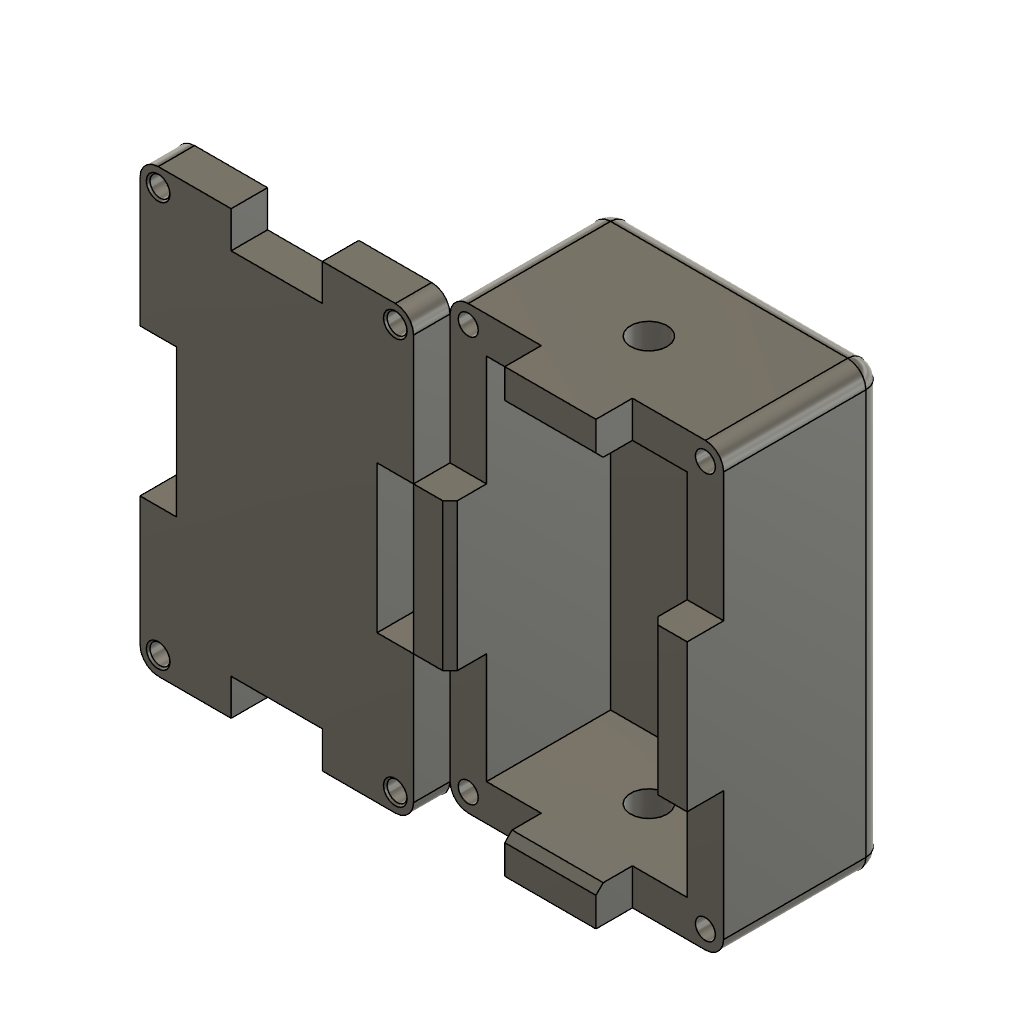
v1_caja (Autodesk Fusion 360 design; units mm, degrees)
part number: 2026-10-22-22-34-57-953
Autodesk Fusion 360 part; units mm, degrees
sketch "Sketch1" plane through (0, 0, 0) normal (0, 1, 0) x (1, 0, 0)
  line L0 (0, 0) -> (55, 0)
  line L1 (0, 0) -> (0, -101)
  line L2 (0, -101) -> (55, -101)
  line L3 (55, -101) -> (55, 0)
  dimension "d1" = 55
  dimension "d2" = 101
  dimension "d3" = 55
  constraint coincident L0.start L1.start
  constraint horizontal L0
  constraint perpendicular L0 L1
  constraint perpendicular L1 L2
  measures "d1" distance of L0.start L0.end
  measures "d2" distance of L0.start L1.end
  measures "d3" distance of L1.end L2.end
sketch "Sketch4" plane through (0, 0, 0) normal (0, 1, 0) x (1, 0, 0)
  line L0 (-10, 10) -> (65, 10)
  line L1 (-10, 10) -> (-10, -111)
  line L2 (65, 10) -> (65, -111)
  line L3 (65, -111) -> (-10, -111)
  dimension "d10" = 75
  dimension "d11" = 121
  dimension "d12" = 121
  constraint horizontal L0
  constraint perpendicular L0 L1
  constraint perpendicular L0 L2
  measures "d10" distance of L0.start L0.end
  measures "d11" distance of L0.start L1.end
  measures "d12" distance of L0.end L2.end
extrude "Extrude2" add sketch "Sketch4" along normal blind 54 makes body 1
move_body "Move3" bodies 1 to x (1, 0, 0) y (0, 1, 0) z (0, 0, 1) at (10, 0, 10)
sketch "Sketch5" plane through (0, 54, 0) normal (0, 1, 0) x (-1, 0, 0)
  line L0 (0, 0) -> (0, 121)
  line L1 (0, 121) -> (-75, 121)
  line L2 (-75, 121) -> (-75, 0)
  line L3 (-75, 0) -> (0, 0)
  line L4 (0, 121) -> (-25, 121)
  line L5 (-25, 121) -> (-25, 111)
  line L6 (-25, 111) -> (-50, 111)
  line L7 (-50, 111) -> (-50, 121)
  line L8 (-50, 121) -> (-75, 121)
  line L9 (-75, 121) -> (-75, 80.6667)
  line L10 (-75, 80.6667) -> (-65, 80.6667)
  line L11 (-65, 80.6667) -> (-65, 40.3333)
  line L12 (-65, 40.3333) -> (-75, 40.3333)
  line L13 (-75, 40.3333) -> (-75, 0)
  line L14 (0, 121) -> (0, 80.6667)
  line L15 (0, 80.6667) -> (-10, 80.6667)
  line L16 (-10, 80.6667) -> (-10, 40.3333)
  line L17 (-10, 40.3333) -> (0, 40.3333)
  line L18 (0, 40.3333) -> (0, 0)
  line L19 (0, 0) -> (-25, 0)
  line L20 (-25, 0) -> (-25, 10)
  line L21 (-25, 10) -> (-50, 10)
  line L22 (-50, 10) -> (-50, 0)
  line L23 (-50, 0) -> (-75, 0)
  dimension "d15" = 75
  dimension "d17" = 25
  dimension "d18" = 10
  dimension "d19" = 25
  dimension "d20" = 40.3333
  dimension "d21" = 40.3333
  dimension "d22" = 40.3333
  dimension "d23" = 40.3333
  dimension "d24" = 10
  dimension "d25" = 40.3333
  dimension "d26" = 40.3333
  dimension "d27" = 25
  dimension "d28" = 10
  dimension "d29" = 25
  constraint coincident L0.end L1.start
  constraint perpendicular L4 L5
  constraint perpendicular L5 L6
  constraint coincident L1.end L2.start
  constraint perpendicular L10 L11
  constraint coincident L2.end L3.start
  constraint perpendicular L4 L14
  constraint perpendicular L0 L15
  constraint perpendicular L15 L16
  constraint coincident L0.start L3.end
  constraint perpendicular L3 L20
  constraint perpendicular L20 L21
  measures "d15" distance of L0.start L2.end
  measures "d17" distance of L0.end L4.end
  measures "d18" distance of L4.end L5.end
  measures "d19" distance of L5.end L6.end
  measures "d20" distance of L1.end L9.end
  measures "d21" distance of L10.end L11.end
  measures "d22" distance of L12.end L2.end
  measures "d23" distance of L0.end L14.end
  measures "d24" distance of L14.end L15.end
  measures "d25" distance of L15.end L16.end
  measures "d26" distance of L17.end L0.start
  measures "d27" distance of L0.start L19.end
  measures "d28" distance of L19.end L20.end
  measures "d29" distance of L20.end L21.end
extrude "Extrude3" cut sketch "Sketch5" against normal blind 10 contours L0 L1 L2 L3 L4 L5 L6 L7 L8 L9 L10 L11 L12 L13 L14 L15 L16 L17 L18 L19 L20 L21 L22 L23 bodies 1
extrude "Extrude4" add sketch "Sketch5" against normal blind 10 separate body contours L0 L1 L2 L3 L4 L5 L6 L7 L8 L9 L10 L11 L12 L13 L14 L15 L16 L17 L18 L19 L20 L21 L22 L23 makes body 2
move_body "Move4" bodies 2 to x (1, 0, 0) y (0, 1, 0) z (0, 0, 1) at (0, 10, 0)
move_body "Move5" bodies 2 to x (1, 0, 0) y (0, 1, 0) z (0, 0, 1) at (-75, 0, 0)
extrude "Extrude5" add sketch "Sketch1" along normal blind 34 separate body makes body 3
move_body "Move6" bodies 3 to x (1, 0, 0) y (0, 1, 0) z (0, 0, 1) at (10, 0, 0)
move_body "Move7" bodies 3 to x (1, 0, 0) y (0, 1, 0) z (0, 0, 1) at (0, 10, 0)
move_body "Move8" bodies 3 to x (1, 0, 0) y (0, 1, 0) z (0, 0, 1) at (0, 0, 10)
combine "Combine1" operation cut target body 1 tool bodies 3
move_body "Move9" bodies 1 to x (1, 0, 0) y (0, 0, 1) z (0, -1, 0) at (0, 120.5, 0.5)
move_body "Move10" bodies 2 to x (1, 0, 0) y (0, 0, 1) z (0, -1, 0) at (0, 124.5, -3.5)
move_body "Move11" bodies 2 to x (1, 0, 0) y (0, 1, 0) z (0, 0, 1) at (0, -16.492, 0)
move_body "Move12" bodies 2 to x (1, 0, 0) y (0, 1, 0) z (0, 0, 1) at (0, 16.492, 0)
move_body "Move13" bodies 1 to x (1, 0, 0) y (0, 1, 0) z (0, 0, 1) at (0, 0.5, 0)
move_body "Move14" bodies 2 to x (1, 0, 0) y (0, 1, 0) z (0, 0, 1) at (0, -3.5, 0)
sketch "Sketch6" plane through (0, 0, 0.5) normal (0, 0, -1) x (-1, 0, 0)
  line L0 (0, 0) -> (0, 121)
  line L1 (0, 121) -> (-75, 121)
  line L2 (-75, 121) -> (-75, 0)
  line L3 (-75, 0) -> (0, 0)
  circle A0 centre (-37.5, 60.5) radius 7.5
  dimension "d36" = 15
  measures "d36" diameter of A0
copy_body "CopyPasteBodies1" bodies 1 makes body 4
extrude "Extrude6" cut sketch "Sketch6" against normal blind 10 contours A0 bodies 1
fillet "Fillet1" radius 5 1 edges at (37.5, 121, 0.5) on bodies 1
fillet "Fillet2" radius 5 3 edges at (0, 58, 0.5) (0, 119.5355, 1.9645) (0, 121, 25) on bodies 1
fillet "Fillet3" radius 5 3 edges at (75, 121, 25) (75, 119.5355, 1.9645) (75, 58, 0.5) on bodies 1
fillet "Fillet4" radius 5 5 edges at (75, 0, 25) (73.5355, 0, 1.9645) (37.5, 0, 0.5) (1.4645, 0, 1.9645) (0, 0, 25) on bodies 1
chamfer "Chamfer1" distance 2 angle 45 1 edges at (10, 60.5, 54.5) tangent chain off on bodies 1
chamfer "Chamfer2" distance 2 angle 45 1 edges at (65, 60.5, 54.5) tangent chain off on bodies 1
chamfer "Chamfer3" distance 2 angle 45 1 edges at (37.5, 111, 54.5) tangent chain off on bodies 1
chamfer "Chamfer4" distance 2 angle 45 1 edges at (37.5, 10, 54.5) tangent chain off on bodies 1
sketch "Sketch7" plane through (0, 121, 0) normal (0, 1, 0) x (-1, 0, 0)
  line L0 (-70, 44.5) -> (-70, 5.5)
  line L1 (-70, 5.5) -> (-5, 5.5)
  line L2 (-5, 5.5) -> (-5, 44.5)
  line L3 (-5, 44.5) -> (-25, 44.5)
  line L4 (-25, 44.5) -> (-25, 54.5)
  line L5 (-25, 54.5) -> (-50, 54.5)
  line L6 (-50, 54.5) -> (-50, 44.5)
  line L7 (-50, 44.5) -> (-70, 44.5)
  circle A0 centre (-37.5, 27.5) radius 8
  circle A1 centre (-37.5, 27.5) radius 5
  dimension "d52" = 16
  dimension "d76" = 10
  constraint concentric A0 A1
  measures "d52" diameter of A0
  measures "d76" diameter of A1
extrude "Extrude7" cut sketch "Sketch7" against normal blind 10 contours A0 | A1 bodies 1
move_body "Move15" bodies 2 to x (1, 0, 0) y (0, 1, 0) z (0, 0, 1) at (75, 0, 0)
fillet "Fillet5" radius 5 1 edges at (75, 121, 55.5) on bodies 2
fillet "Fillet6" radius 5 1 edges at (0, 121, 55.5) on bodies 2
fillet "Fillet7" radius 5 1 edges at (75, 0, 55.5) on bodies 2
fillet "Fillet8" radius 5 1 edges at (0, 0, 55.5) on bodies 2
move_body "Move16" bodies 2 to x (1, 0, 0) y (0, 1, 0) z (0, 0, 1) at (0, 0, -6)
sketch "Sketch8" plane through (0, 0, 54.5) normal (0, 0, 1) x (1, 0, 0)
  arc A0 (0, 5) -> (5, 0) centre (5, 5) ccw
  line L0 (5, 0) -> (25, 0)
  line L1 (25, 0) -> (25, 10)
  line L2 (25, 10) -> (50, 10)
  line L3 (50, 10) -> (50, 0)
  line L4 (50, 0) -> (70, 0)
  arc A1 (70, 0) -> (75, 5) centre (70, 5) ccw
  line L5 (75, 5) -> (75, 40.3333)
  line L6 (75, 40.3333) -> (65, 40.3333)
  line L7 (65, 40.3333) -> (65, 80.6667)
  line L8 (65, 80.6667) -> (75, 80.6667)
  line L9 (75, 80.6667) -> (75, 116)
  arc A2 (75, 116) -> (70, 121) centre (70, 116) ccw
  line L10 (70, 121) -> (50, 121)
  line L11 (50, 121) -> (50, 111)
  line L12 (50, 111) -> (25, 111)
  line L13 (25, 111) -> (25, 121)
  line L14 (25, 121) -> (5, 121)
  arc A3 (5, 121) -> (0, 116) centre (5, 116) ccw
  line L15 (0, 116) -> (0, 80.6667)
  line L16 (0, 80.6667) -> (10, 80.6667)
  line L17 (10, 80.6667) -> (10, 40.3333)
  line L18 (10, 40.3333) -> (0, 40.3333)
  line L19 (0, 40.3333) -> (0, 5)
  circle A4 centre (5, 5) radius 2.75
  circle A5 centre (70, 5) radius 2.75
  circle A6 centre (70, 116) radius 2.75
  circle A7 centre (5, 116) radius 2.75
  dimension "d63" = 5.5
  dimension "d64" = 5.5
  dimension "d65" = 5.5
  dimension "d66" = 5.5
  constraint concentric A0 A4
  constraint concentric A1 A5
  constraint concentric A2 A6
  constraint concentric A3 A7
  measures "d63" diameter of A4
  measures "d64" diameter of A5
  measures "d65" diameter of A6
  measures "d66" diameter of A7 A0
extrude "Extrude8" cut sketch "Sketch8" against normal blind 22 contours A4 | A5 | A6 | A7 bodies 1 2
chamfer "Chamfer5" distance 0.5 angle 45 4 edges at (67.4361, 5.9944, 54.5) (67.4361, 116.9944, 54.5) (2.4361, 116.9944, 54.5) (2.4361, 5.9944, 54.5) tangent chain off on bodies 2
move_body "Move17" bodies 2 to x (1, 0, 0) y (0, 1, 0) z (0, 0, 1) at (-75, 0, 0)
chamfer "Chamfer6" distance 1 angle 45 1 edges at (44.9586, 121, 30.3929) tangent chain off on bodies 1
chamfer "Chamfer7" distance 2 angle 45 1 edges at (44.4925, 63.2121, 0.5) tangent chain off on bodies 1
sketch "Sketch9" plane through (0, 0, 0.5) normal (0, 0, -1) x (-1, 0, 0)
  line L0 (-70, 5) -> (-5, 5)
  line L1 (-5, 5) -> (-5, 116)
  line L2 (-5, 116) -> (-70, 116)
  line L3 (-70, 116) -> (-70, 5)
  circle A0 centre (-37.5, 60.5) radius 9.5
  line L4 (-51, 74) -> (-26, 74)
  line L5 (-26, 74) -> (-26, 47)
  line L6 (-26, 47) -> (-51, 47)
  line L7 (-51, 47) -> (-51, 74)
  constraint horizontal L4
  constraint vertical L5
  constraint horizontal L6
  constraint vertical L7
extrude "Extrude9" add sketch "Sketch9" against normal blind 10 contours A0 | L4 L5 L6 L7 bodies 1
sketch "Sketch10" plane through (0, 121, 0) normal (0, 1, 0) x (-1, 0, 0)
  line L0 (-70, 44.5) -> (-70, 5.5)
  line L1 (-70, 5.5) -> (-5, 5.5)
  line L2 (-5, 5.5) -> (-5, 44.5)
  line L3 (-5, 44.5) -> (-25, 44.5)
  line L4 (-25, 44.5) -> (-25, 54.5)
  line L5 (-25, 54.5) -> (-50, 54.5)
  line L6 (-50, 54.5) -> (-50, 44.5)
  line L7 (-50, 44.5) -> (-70, 44.5)
  circle A0 centre (-37.5, 27.5) radius 9
  line L8 (-50, 38) -> (-25, 38)
  line L9 (-25, 38) -> (-25, 16)
  line L10 (-25, 16) -> (-50, 16)
  line L11 (-50, 16) -> (-50, 38)
  constraint horizontal L8
  constraint vertical L9
  constraint horizontal L10
  constraint vertical L11
extrude "Extrude10" add sketch "Sketch10" against normal blind 10 contours A0 | L8 L9 L10 L11 bodies 1
extrude "Extrude11" cut sketch "Sketch7" against normal blind 160 contours A1 bodies 1
hidden bodies 4
equation "d17 = ( 75 / 3 ) * 1 mm"
equation "d20 = ( 121 / 3 ) * 1 mm"
equation "d21 = ( 121 / 3 ) * 1 mm"
equation "d22 = ( 121 / 3 ) * 1 mm"
equation "d23 = ( 121 / 3 ) * 1 mm"
equation "d25 = ( 121 / 3 ) * 1 mm"
equation "d26 = ( 121 / 3 ) * 1 mm"
named bodies: "caja", "tapa", "copia caja sin cambios"
